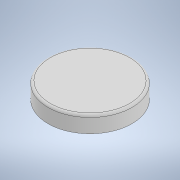
# Autodesk Inventor part: capac_suport monede
Saved by Autodesk Inventor 2022.6 (Build 266554000, 554)
## iProperties
Created: 2026-09-04
Part Number: capac_suport monede
Material: Generic
Document SubType Name: Modeling
Designer: Dragos Macovei
Density: 1 g/cm^3
Appearance: Default
Author: Dragos Macovei
Autodesk Inventor part; units mm, degrees
ref_plane "YZ Plane" through (0, 0, 0) normal (1, 0, 0) x (0, 1, 0)
ref_plane "XZ Plane" through (0, 0, 0) normal (0, 1, 0) x (-1, 0, 0)
ref_plane "XY Plane" through (0, 0, 0) normal (0, 0, 1) x (1, 0, 0)
sketch "Sketch1" plane through (0, 0, 0) normal (0, 1, 0) x (-1, 0, 0)
  circle A0 centre (0, 0) radius 15.4
  circle A1 centre (0, 0) radius 17.9
  dimension "d0" = 30.8
  dimension "d1" = 35.8
  constraints: 2 centre point, 2 coincident
  measures "d0" diameter of A0
  measures "d1" diameter of A1
extrude "Extrusion1" add sketch "Sketch1" against normal blind 7
sketch "Sketch2" plane through (0, 0, 0) normal (0, 1, 0) x (1, 0, 0)
  circle A0 centre (0, 0) radius 17.9 projected
  circle A1 centre (0, 0) radius 15.4 projected
extrude "Extrusion2" add sketch "Sketch2" against normal blind 1 contours A1
fillet "Fillet1" radius 1 1 edges at (17.9, 0, 0)
fillet "Fillet2" radius 1 1 edges at (15.4, -7, 0)
body "Solid1"
